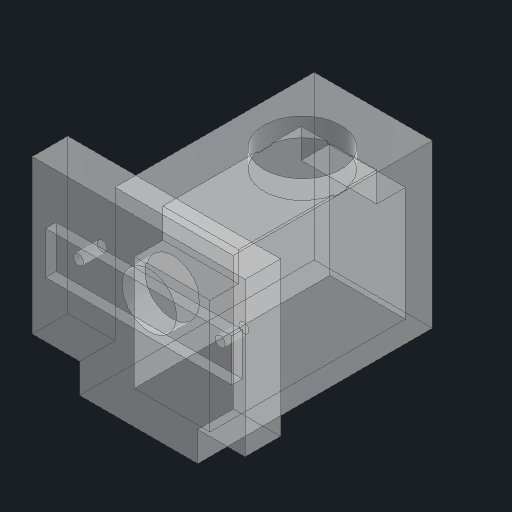
# Autodesk Inventor part: PEN-008L
Saved by Autodesk Inventor 2027.1 (Build 311270010, 270A)
## iProperties
Created: 2026-10-28
Part Number: PEN-008L
Material: PETG 3D Print
Description: Leg, left, PETG
Document SubType Name: Modeling
Designer: shyan
Mass: 17.7365 g
Surface Area: 82.98 cm^2
Volume: 13.9658 cm^3
Density: 1.27 g/cm^3
Appearance: Polycarbonate - Clear
Author: shyan
Autodesk Inventor part; units mm, degrees
ref_plane "sk_legtop_plane" through (0, 0, -18.3) normal (0, 0, 1) x (1, 0, 0)
sketch "sk_legtop" plane through (0, 0, -18.3) normal (0, 0, 1) x (1, 0, 0)
  line L0 (0, 0) -> (60, 0) construction
  line L1 (0, 0) -> (0, 60) construction
  line L2 (-44, -13) -> (-8, -13)
  line L3 (-8, -13) -> (-8, 13)
  line L4 (-8, 13) -> (-44, 13)
  line L5 (-44, 13) -> (-44, -13)
  dimension "d1" = 36
  dimension "d2" = 26
  dimension "d3" = 44
  constraints: 12 end point, 2 parallel, 1 horizontal, 1 perpendicular, 5 other
  measures "d1" distance of L2.start L2.end
  measures "d2" distance of L2.end L3.end
  measures "d3" horizontal distance of L0.start L4.end
extrude "TopPlate" add sketch "sk_legtop" along normal blind 6
ref_plane "sk_legbody_plane" through (0, 0, -52) normal (0, 0, 1) x (1, 0, 0)
sketch "sk_legbody" plane through (0, 0, -52) normal (0, 0, 1) x (1, 0, 0)
  line L0 (0, 0) -> (60, 0) construction
  line L1 (0, 0) -> (0, 60) construction
  line L2 (-36, -18) -> (-16, -18)
  line L3 (-16, -18) -> (-16, 9.5)
  line L4 (-16, 9.5) -> (-36, 9.5)
  line L5 (-36, 9.5) -> (-36, -18)
  dimension "d7" = 20
  dimension "d8" = 27.5
  dimension "d9" = 36
  dimension "d10" = 18
  constraints: 12 end point, 2 parallel, 1 horizontal, 1 perpendicular, 4 other
  measures "d7" distance of L2.start L2.end
  measures "d8" distance of L2.end L3.end
  measures "d9" horizontal distance of L0.start L4.end
  measures "d10" vertical distance of L0.start L2.start
extrude "LegBody" add sketch "sk_legbody" along normal blind 39.7
ref_plane "sk_horn_pocket_plane" through (0, 0, -12.3) normal (0, 0, 1) x (1, 0, 0)
sketch "sk_horn_pocket" plane through (0, 0, -12.3) normal (0, 0, 1) x (1, 0, 0)
  line L0 (0, 0) -> (60, 0) construction
  line L1 (0, 0) -> (0, 60) construction
  line L2 (-41.75, -3.6) -> (-10.25, -3.6)
  line L3 (-10.25, -3.6) -> (-10.25, 3.6)
  line L4 (-10.25, 3.6) -> (-41.75, 3.6)
  line L5 (-41.75, 3.6) -> (-41.75, -3.6)
  dimension "d14" = 31.5
  dimension "d15" = 7.2
  dimension "d16" = 41.75
  constraints: 12 end point, 2 parallel, 1 horizontal, 1 perpendicular, 5 other
  measures "d14" distance of L2.start L2.end
  measures "d15" distance of L2.end L3.end
  measures "d16" horizontal distance of L0.start L4.end
extrude "HornPocket" cut sketch "sk_horn_pocket" against normal blind 1.8
ref_plane "sk_hub_clr_plane" through (0, 0, -14.1) normal (0, 0, 1) x (1, 0, 0)
sketch "sk_hub_clr" plane through (0, 0, -14.1) normal (0, 0, 1) x (1, 0, 0)
  line L0 (0, 0) -> (60, 0) construction
  line L1 (0, 0) -> (0, 60) construction
  circle A0 centre (-26, 0) radius 4.6
  circle A1 centre (-14, 0) radius 0.85
  circle A2 centre (-38, 0) radius 0.85
  dimension "d20" = 9.2
  dimension "d21" = 26
  dimension "d22" = 1.7
  dimension "d23" = 14
  dimension "d24" = 1.7
  dimension "d25" = 38
  constraints: 4 end point, 3 centre point, 3 point on line, 4 other
  measures "d20" diameter of A0
  measures "d21" distance of L0.start A0.centre
  measures "d22" diameter of A1
  measures "d23" distance of L0.start A1.centre
  measures "d24" diameter of A2
  measures "d25" distance of L0.start A2.centre
extrude "HubAndHornScrews" cut sketch "sk_hub_clr" against normal blind 4
ref_plane "sk_ank_case_plane" through (0, -18, 0) normal (0, 1, 0) x (-1, 0, 0)
sketch "sk_ank_case" plane through (0, -18, 0) normal (0, 1, 0) x (-1, 0, 0)
  line L0 (0, 0) -> (60, 0) construction
  line L1 (0, 0) -> (0, 60) construction
  line L2 (19.6, -46.2) -> (32.4, -46.2)
  line L3 (32.4, -46.2) -> (32.4, -22.8)
  line L4 (32.4, -22.8) -> (19.6, -22.8)
  line L5 (19.6, -22.8) -> (19.6, -46.2)
  dimension "d29" = 12.8
  dimension "d30" = 23.4
  dimension "d31" = 19.6
  dimension "d32" = 46.2
  constraints: 12 end point, 2 parallel, 1 horizontal, 1 perpendicular, 4 other
  measures "d29" distance of L2.start L2.end
  measures "d30" distance of L2.end L3.end
  measures "d31" horizontal distance of L0.start L4.end
  measures "d32" vertical distance of L0.start L2.start
extrude "AnkleCasePocket" cut sketch "sk_ank_case" along normal blind 24.3
ref_plane "sk_ank_tabs_plane" through (0, -18, 0) normal (0, 1, 0) x (-1, 0, 0)
sketch "sk_ank_tabs" plane through (0, -18, 0) normal (0, 1, 0) x (-1, 0, 0)
  line L0 (0, 0) -> (60, 0) construction
  line L1 (0, 0) -> (0, 60) construction
  line L2 (19.6, -51.05) -> (32.4, -51.05)
  line L3 (32.4, -51.05) -> (32.4, -17.95)
  line L4 (32.4, -17.95) -> (19.6, -17.95)
  line L5 (19.6, -17.95) -> (19.6, -51.05)
  dimension "d36" = 12.8
  dimension "d37" = 33.1
  dimension "d38" = 19.6
  dimension "d39" = 51.05
  constraints: 12 end point, 2 parallel, 1 horizontal, 1 perpendicular, 4 other
  measures "d36" distance of L2.start L2.end
  measures "d37" distance of L2.end L3.end
  measures "d38" horizontal distance of L0.start L4.end
  measures "d39" vertical distance of L0.start L2.start
extrude "AnkleTabRecess" cut sketch "sk_ank_tabs" along normal blind 19.3
ref_plane "sk_spline_exit_plane" through (0, 6, 0) normal (0, 1, 0) x (-1, 0, 0)
sketch "sk_spline_exit" plane through (0, 6, 0) normal (0, 1, 0) x (-1, 0, 0)
  line L0 (0, 0) -> (60, 0) construction
  line L1 (0, 0) -> (0, 60) construction
  circle A0 centre (26, -40) radius 6.5
  dimension "d43" = 13
  dimension "d44" = 26
  dimension "d45" = 40
  constraints: 4 end point, 1 centre point, 4 other
  measures "d43" diameter of A0
  measures "d44" horizontal distance of L0.start A0.centre
  measures "d45" vertical distance of L0.start A0.centre
extrude "SplineExit" cut sketch "sk_spline_exit" along normal blind 5.5
ref_plane "sk_ank_screws_plane" through (0, 1.3, 0) normal (0, 1, 0) x (-1, 0, 0)
sketch "sk_ank_screws" plane through (0, 1.3, 0) normal (0, 1, 0) x (-1, 0, 0)
  line L0 (0, 0) -> (60, 0) construction
  line L1 (0, 0) -> (0, 60) construction
  circle A0 centre (26, 59.25) radius 0.85
  circle A1 centre (26, 31.75) radius 0.85
  dimension "d49" = 1.7
  dimension "d50" = 26
  dimension "d51" = 59.25
  dimension "d52" = 1.7
  dimension "d53" = 26
  dimension "d54" = 31.75
  constraints: 4 end point, 2 centre point, 4 other
  measures "d49" diameter of A0
  measures "d50" horizontal distance of L0.start A0.centre
  measures "d51" vertical distance of L0.start A0.centre
  measures "d52" diameter of A1
  measures "d53" horizontal distance of L0.start A1.centre
  measures "d54" vertical distance of L0.start A1.centre
extrude "AnkleTabScrews" cut sketch "sk_ank_screws" along normal blind 6
ref_plane "pl_hipX" through (-26, 0, 0) normal (1, 0, 0) x (0, 1, 0)
ref_plane "pl_ankZ" through (0, 0, -40) normal (0, 0, 1) x (1, 0, 0)
equation "\"d1\" = legtop_W"
equation "\"d2\" = legtop_D"
equation "\"d3\" = hip_x + 0.5 * legtop_W"
equation "\"d4\" = legtop_T"
equation "\"d7\" = leg_W"
equation "\"d8\" = leg_Yf - leg_Yb"
equation "\"d9\" = hip_x + 0.5 * leg_W"
equation "\"d10\" = -leg_Yb"
equation "\"d11\" = leg_topz - leg_botz"
equation "\"d14\" = horn_len"
equation "\"d15\" = horn_hub"
equation "\"d16\" = hip_x + 0.5 * horn_len"
equation "\"d17\" = horn_T"
equation "\"d20\" = horn_hub + hornhub_clr"
equation "\"d21\" = hip_x"
equation "\"d22\" = m2_pilot"
equation "\"d23\" = hip_x - horn_screw_x"
equation "\"d24\" = m2_pilot"
equation "\"d25\" = hip_x + horn_screw_x"
equation "\"d26\" = hub_depth"
equation "\"d29\" = sv_W + 2 * clr"
equation "\"d30\" = sv_L + 2 * clr"
equation "\"d31\" = -0.5 * sv_W + hip_x - clr"
equation "\"d32\" = sv_shaft - Z_ankle + clr"
equation "\"d33\" = clr + ank_shaftY - leg_Yb"
equation "\"d36\" = sv_W + 2 * clr"
equation "\"d37\" = sv_tab + 2 * clr"
equation "\"d38\" = -0.5 * sv_W + hip_x - clr"
equation "\"d39\" = 0.5 * sv_tab - 0.5 * sv_L - Z_ankle + sv_shaft + clr"
equation "\"d40\" = ank_ledgeY - leg_Yb"
equation "\"d44\" = hip_x"
equation "\"d45\" = -Z_ankle"
equation "\"d49\" = m2_pilot"
equation "\"d50\" = hip_x"
equation "\"d51\" = -sv_shaft - Z_ankle + 0.5 * sv_L + 0.5 * sv_pitch"
equation "\"d52\" = m2_pilot"
equation "\"d53\" = hip_x"
equation "\"d54\" = -sv_shaft - Z_ankle + 0.5 * sv_L - 0.5 * sv_pitch"
equation "\"d55\" = ins_L"
equation "\"clr\" = 0.3"
equation "\"wall\" = 2.4"
equation "\"sv_L\" = 22.8"
equation "\"sv_W\" = 12.2"
equation "\"sv_H\" = 22.7"
equation "\"sv_full\" = 28.5"
equation "\"sv_tab\" = 32.5"
equation "\"sv_tabT\" = 2.5"
equation "\"sv_tabZ\" = 15.5"
equation "\"sv_pitch\" = 27.5"
equation "\"sv_shaft\" = 5.9"
equation "\"sv_dome\" = 12"
equation "\"sv_domeH\" = 3.3"
equation "\"sv_spline\" = 4.8"
equation "\"m2_pilot\" = 1.7"
equation "\"horn_len\" = 31.5"
equation "\"horn_hub\" = 7.2"
equation "\"horn_tip\" = 4.5"
equation "\"horn_T\" = 1.8"
equation "\"horn_hubH\" = 3.8"
equation "\"ins_d\" = 4"
equation "\"ins_L\" = 6"
equation "\"m3\" = 3.4"
equation "\"nut_af\" = 5.8"
equation "\"hip_x\" = 26"
equation "\"plate_T\" = 5"
equation "\"col_H\" = 16"
equation "\"tray_T\" = 3"
equation "\"bodyW0\" = 96"
equation "\"bodyW35\" = 106"
equation "\"bodyD35\" = 86"
equation "\"bodyW85\" = 92"
equation "\"bodyD85\" = 74"
equation "\"bodyW112\" = 64"
equation "\"bodyD112\" = 56"
equation "\"Z_sec1\" = 35"
equation "\"Z_sec2\" = 85"
equation "\"Z_sec3\" = 112"
equation "\"Z_flip\" = 78"
equation "\"Z_bridge\" = 98"
equation "\"bat_W\" = 77"
equation "\"bat_D\" = 41"
equation "\"bat_H\" = 21"
equation "\"esp_W\" = 55"
equation "\"esp_D\" = 28"
equation "\"esp_H\" = 13"
equation "\"pcb_D\" = 38"
equation "\"pcb_T\" = 1.6"
equation "\"bk_D\" = 22"
equation "\"df_W\" = 49"
equation "\"df_D\" = 32"
equation "\"df_H\" = 12"
equation "\"sw_W\" = 21"
equation "\"sw_D\" = 15"
equation "\"sw_H\" = 25"
equation "\"usb_cut_W\" = 12"
equation "\"usb_cut_H\" = 7"
equation "\"usb_pitch\" = 28"
equation "\"leg_W\" = 20"
equation "\"leg_Yb\" = -18"
equation "\"leg_Yf\" = 9.5"
equation "\"leg_botz\" = -52"
equation "\"legtop_W\" = 36"
equation "\"legtop_D\" = 26"
equation "\"legtop_T\" = 6"
equation "\"Z_ankle\" = -40"
equation "\"ank_shaftY\" = 6"
equation "\"hornhub_clr\" = 2"
equation "\"horn_screw_x\" = 12"
equation "\"hub_depth\" = 4"
equation "\"leg_topz\" = -sv_domeH + sv_tabZ - sv_H - horn_T"
equation "\"hip_X\" = -hip_x"
equation "\"d0\" = leg_topz - legtop_T"
equation "\"d6\" = leg_botz"
equation "\"ank_ledgeY\" = 1.3"
equation "\"d13\" = leg_topz"
equation "\"d19\" = leg_topz - horn_T"
equation "\"d28\" = leg_Yb"
equation "\"d35\" = leg_Yb"
equation "\"d42\" = ank_shaftY"
equation "\"d48\" = ank_ledgeY"
equation "\"d57\" = hip_X"
body "Solid1"
